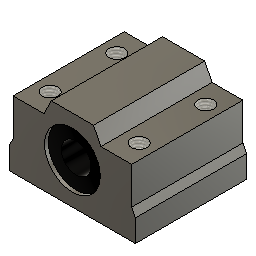
SC8UU SCS8UU Linear Rail Bearing v4 (Autodesk Fusion 360 design; units mm, degrees)
Autodesk Fusion 360 part; units mm, degrees
sketch "Sketch1" plane through (0, 0, 0) normal (0, 0, 1) x (1, 0, 0)
  circle A0 centre (0, 0) radius 4
  line L0 (-16, 7) -> (-7.6922, 7)
  circle A1 centre (0, 0) radius 7.5
  line L1 (16, 7) -> (16, -3)
  line L2 (16, -3) -> (17, -5)
  line L3 (5.6922, 11) -> (0, 11)
  line L4 (7.6922, 7) -> (16, 7)
  line L5 (-5.6922, 11) -> (0, 11)
  line L6 (17, -5) -> (17, -11)
  line L7 (5.6922, 11) -> (7.6922, 7)
  line L8 (-17, -5) -> (-16, -3)
  line L9 (-7.6922, 7) -> (-5.6922, 11)
  line L10 (-0.0559, -11) -> (-17, -11)
  line L11 (17, -11) -> (-0.0559, -11)
  line L12 (-16, -3) -> (-16, 7)
  line L13 (-17, -11) -> (-17, -5)
  dimension "d1" = 8
  dimension "d2" = 22
  dimension "d3" = 34
  dimension "d4" = 18
  dimension "d5" = 6
  dimension "d6" = 11
  dimension "d7" = 16
  dimension "d8" = 15
  dimension "d9" = 8
  constraint coincident A0.centre A1.centre
  constraint horizontal L10
  constraint perpendicular L10 L13
  constraint parallel L12 L13
  constraint perpendicular L0 L13
  constraint parallel L8 L9
  constraint perpendicular L5 L13
  constraint parallel L2 L7
  constraint collinear L0 L4
  constraint collinear L3 L5
  measures "d1" diameter of A0
  measures "d2" distance of L3 L11
  measures "d3" distance of L6 L13
  measures "d4" distance of L0 L10
  measures "d5" distance of L8.start L10
  measures "d6" vertical distance of A0.centre L10.start
  measures "d7" distance of A0.centre L1 L2.start
  measures "d8" diameter of A1
  measures "d9" distance of L8.end L10
extrude "Extrude1" add sketch "Sketch1" along normal blind 30 contours L0 L1 L2 L3 L4 L5 L6 L7 L8 L9 L10 L11 L12 L13 | A1
extrude "Extrude2" cut sketch "Sketch1" along normal blind 1 contours A1
sketch "Sketch2" plane through (0, 0, 30) normal (0, 0, 1) x (1, 0, 0)
  circle A0 centre (0, 0) radius 4
  line L0 (5.6922, 11) -> (-5.6922, 11)
  line L1 (-5.6922, 11) -> (-7.6922, 7)
  line L2 (-7.6922, 7) -> (-16, 7)
  line L3 (-16, 7) -> (-16, -3)
  line L4 (-16, -3) -> (-17, -5)
  line L5 (-17, -5) -> (-17, -11)
  line L6 (-17, -11) -> (17, -11)
  line L7 (17, -11) -> (17, -5)
  line L8 (17, -5) -> (16, -3)
  line L9 (16, -3) -> (16, 7)
  line L10 (16, 7) -> (7.6922, 7)
  line L11 (7.6922, 7) -> (5.6922, 11)
  circle A1 centre (0, 0) radius 7.5
  circle A2 centre (0, 0) radius 4
  line L12 (5.6922, 11) -> (-5.6922, 11)
  line L13 (-5.6922, 11) -> (-7.6922, 7)
  line L14 (-7.6922, 7) -> (-16, 7)
  line L15 (-16, 7) -> (-16, -3)
  line L16 (-16, -3) -> (-17, -5)
  line L17 (-17, -5) -> (-17, -11)
  line L18 (-17, -11) -> (17, -11)
  line L19 (17, -11) -> (17, -5)
  line L20 (17, -5) -> (16, -3)
  line L21 (16, -3) -> (16, 7)
  line L22 (16, 7) -> (7.6922, 7)
  line L23 (7.6922, 7) -> (5.6922, 11)
extrude "Extrude3" cut sketch "Sketch2" against normal blind 1 contours A1
sketch "Sketch4" plane through (0, -11, 0) normal (0, -1, 0) x (1, 0, 0)
  line L0 (-17, 0) -> (17, 0)
  line L1 (17, 0) -> (17, 30)
  line L2 (17, 30) -> (-17, 30)
  line L3 (-17, 30) -> (-17, 0)
  line L4 (-17, 15) -> (17, 15) construction
  line L5 (-17, 0) -> (17, 0)
  line L6 (17, 0) -> (17, 30)
  line L7 (0, 0) -> (0, 30) construction
  line L8 (17, 30) -> (-17, 30)
  line L9 (-17, 30) -> (-17, 0)
  line L10 (-17, 0) -> (17, 0)
  line L11 (17, 0) -> (17, 30)
  line L12 (17, 30) -> (-17, 30)
  line L13 (-17, 30) -> (-17, 0)
  point P0 (-12, 24)
  point P1 (-12, 6)
  point P2 (12, 24)
  point P3 (12, 6)
  dimension "d22" = 5
  dimension "d23" = 5
  dimension "d24" = 9
  constraint coincident L7.start origin
  constraint midpoint L7.end L8
  constraint midpoint L4.start L9
  constraint midpoint L4.end L6
  constraint symmetric P0 P1 L4
  constraint symmetric P0 P2 L7
  constraint symmetric P1 P3 L7
  measures "d22" distance of P1 L9
  measures "d23" distance of P0 L9
  measures "d24" distance of P0 L4
hole "Hole1" at (-12, -11, 24) at (12, -11, 24) at (12, -11, 6) at (-12, -11, 6) direction (0, 1, 0) diameter 4.234 end through all
thread "Thread1" "ISO Metric profile 5.0 M5x0.8 6H"
